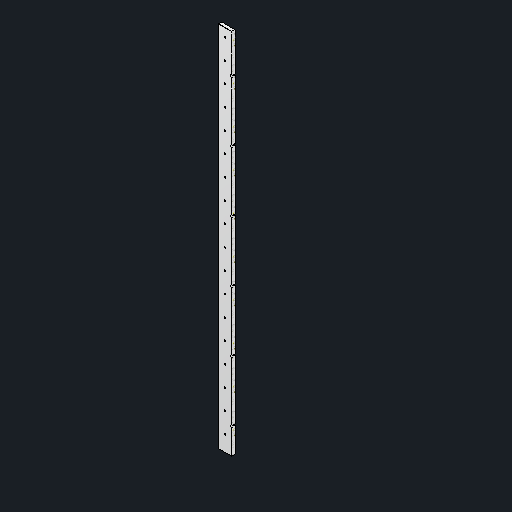
# Autodesk Inventor part: monotaro-bellows-plate
Saved by Autodesk Inventor 2027.1 (Build 311270010, 270A)
## iProperties
Created: 2026-11-14
Part Number: monotaro-bellows-plate
Material: Aluminum 6061
Description: MonotaRO review plate; verify fastener threads, vendor outlines and travel before machining
Document SubType Name: Modeling
Designer: queezz
Density: 2.7 g/cm^3
Appearance: Aluminum - Flat
Author: queezz
Autodesk Inventor part; units mm, degrees
ref_plane "215 x 1235 blank plane" through (0, 0, -55) normal (0, 0, 1) x (1, 0, 0)
sketch "215 x 1235 blank" plane through (0, 0, -55) normal (0, 0, 1) x (1, 0, 0)
  line L0 (-107.5, -339.7289) -> (107.5, -339.7289)
  line L1 (107.5, -339.7289) -> (107.5, 895.2711)
  line L2 (107.5, 895.2711) -> (-107.5, 895.2711)
  line L3 (-107.5, 895.2711) -> (-107.5, -339.7289)
  constraints: 8 end point, 2 parallel, 1 horizontal, 1 perpendicular
extrude "Table plate" add sketch "215 x 1235 blank" along normal blind 10
ref_plane "Wheel sweep edge relief plane" through (0, 0, -45) normal (0, 0, 1) x (1, 0, 0)
sketch "Wheel sweep edge relief" plane through (0, 0, -45) normal (0, 0, 1) x (1, 0, 0)
  line L0 (-75, -342) -> (75, -342)
  line L1 (75, -342) -> (75, -197)
  line L2 (75, -197) -> (-75, -197)
  line L3 (-75, -197) -> (-75, -342)
  constraints: 8 end point, 2 parallel, 1 horizontal, 1 perpendicular
extrude "150 mm open wheel notch" [suppressed]
ref_plane "SBC rail M5 tap pilots layout plane" through (0, 0, -45) normal (0, 0, 1) x (1, 0, 0)
sketch "SBC rail M5 tap pilots layout" plane through (0, 0, -45) normal (0, 0, 1) x (1, 0, 0)
  circle A0 centre (-87.5, -149.7289) radius 2.1
  circle A1 centre (-87.5, -89.7289) radius 2.1
  circle A2 centre (-87.5, -29.7289) radius 2.1
  circle A3 centre (-87.5, 30.2711) radius 2.1
  circle A4 centre (-87.5, 90.2711) radius 2.1
  circle A5 centre (-87.5, 150.2711) radius 2.1
  circle A6 centre (-87.5, 210.2711) radius 2.1
  circle A7 centre (-87.5, 270.2711) radius 2.1
  circle A8 centre (-87.5, 330.2711) radius 2.1
  circle A9 centre (-87.5, 390.2711) radius 2.1
  circle A10 centre (-87.5, 450.2711) radius 2.1
  circle A11 centre (-87.5, 510.2711) radius 2.1
  circle A12 centre (-87.5, 570.2711) radius 2.1
  circle A13 centre (-87.5, 630.2711) radius 2.1
  circle A14 centre (-87.5, 690.2711) radius 2.1
  circle A15 centre (-87.5, 750.2711) radius 2.1
  circle A16 centre (-87.5, 810.2711) radius 2.1
  circle A17 centre (-87.5, 870.2711) radius 2.1
  circle A18 centre (87.5, -149.7289) radius 2.1
  circle A19 centre (87.5, -89.7289) radius 2.1
  circle A20 centre (87.5, -29.7289) radius 2.1
  circle A21 centre (87.5, 30.2711) radius 2.1
  circle A22 centre (87.5, 90.2711) radius 2.1
  circle A23 centre (87.5, 150.2711) radius 2.1
  circle A24 centre (87.5, 210.2711) radius 2.1
  circle A25 centre (87.5, 270.2711) radius 2.1
  circle A26 centre (87.5, 330.2711) radius 2.1
  circle A27 centre (87.5, 390.2711) radius 2.1
  circle A28 centre (87.5, 450.2711) radius 2.1
  circle A29 centre (87.5, 510.2711) radius 2.1
  circle A30 centre (87.5, 570.2711) radius 2.1
  circle A31 centre (87.5, 630.2711) radius 2.1
  circle A32 centre (87.5, 690.2711) radius 2.1
  circle A33 centre (87.5, 750.2711) radius 2.1
  circle A34 centre (87.5, 810.2711) radius 2.1
  circle A35 centre (87.5, 870.2711) radius 2.1
  constraints: 36 centre point
extrude "SBC rail M5 tap pilots" [suppressed]
ref_plane "Lead screw blocks M6 tap pilots layout plane" through (0, 0, -45) normal (0, 0, 1) x (1, 0, 0)
sketch "Lead screw blocks M6 tap pilots layout" plane through (0, 0, -45) normal (0, 0, 1) x (1, 0, 0)
  circle A0 centre (-23, -169.7489) radius 2.5
  circle A1 centre (-23, 750.2911) radius 2.5
  circle A2 centre (23, -169.7489) radius 2.5
  circle A3 centre (23, 750.2911) radius 2.5
  constraints: 4 centre point
extrude "Lead screw blocks M6 tap pilots" [suppressed]
ref_plane "Plate to T-slot M5 clearance layout plane" through (0, 0, -45) normal (0, 0, 1) x (1, 0, 0)
sketch "Plate to T-slot M5 clearance layout" plane through (0, 0, -45) normal (0, 0, 1) x (1, 0, 0)
  circle A0 centre (-92.5, -119.7289) radius 2.75
  circle A1 centre (-92.5, 60.2711) radius 2.75
  circle A2 centre (-92.5, 240.2711) radius 2.75
  circle A3 centre (-92.5, 420.2711) radius 2.75
  circle A4 centre (-92.5, 600.2711) radius 2.75
  circle A5 centre (-92.5, 780.2711) radius 2.75
  circle A6 centre (92.5, -119.7289) radius 2.75
  circle A7 centre (92.5, 60.2711) radius 2.75
  circle A8 centre (92.5, 240.2711) radius 2.75
  circle A9 centre (92.5, 420.2711) radius 2.75
  circle A10 centre (92.5, 600.2711) radius 2.75
  circle A11 centre (92.5, 780.2711) radius 2.75
  constraints: 12 centre point
extrude "Plate to T-slot M5 clearance" [suppressed]
ref_plane "Flush fastener head envelope layout plane" through (0, 0, -45) normal (0, 0, 1) x (1, 0, 0)
sketch "Flush fastener head envelope layout" plane through (0, 0, -45) normal (0, 0, 1) x (1, 0, 0)
  circle A0 centre (-92.5, -119.7289) radius 5
  circle A1 centre (-92.5, 60.2711) radius 5
  circle A2 centre (-92.5, 240.2711) radius 5
  circle A3 centre (-92.5, 420.2711) radius 5
  circle A4 centre (-92.5, 600.2711) radius 5
  circle A5 centre (-92.5, 780.2711) radius 5
  circle A6 centre (92.5, -119.7289) radius 5
  circle A7 centre (92.5, 60.2711) radius 5
  circle A8 centre (92.5, 240.2711) radius 5
  circle A9 centre (92.5, 420.2711) radius 5
  circle A10 centre (92.5, 600.2711) radius 5
  circle A11 centre (92.5, 780.2711) radius 5
  constraints: 12 centre point
extrude "Flush fastener head envelope" [suppressed]
ref_plane "Work Plane7" through (0, 0, -45) normal (0, 0, 1) x (1, 0, 0)
sketch "Straight wheel-end trim layout" plane through (0, 0, -45) normal (0, 0, 1) x (1, 0, 0)
  line L0 (-110, -350) -> (110, -350)
  line L1 (110, -350) -> (110, -196.729)
  line L2 (110, -196.729) -> (-110, -196.729)
  line L3 (-110, -196.729) -> (-110, -350)
  constraints: 8 end point, 2 parallel, 1 horizontal, 1 perpendicular
extrude "Straight wheel-end trim" cut sketch "Straight wheel-end trim layout" against normal blind 10
ref_plane "Work Plane8" through (0, 0, -45) normal (0, 0, 1) x (1, 0, 0)
sketch "SBC rail M6 tap pilot layout" plane through (0, 0, -45) normal (0, 0, 1) x (1, 0, 0)
  circle A0 centre (-87.5, -149.7289) radius 2.5
  circle A1 centre (-87.5, -89.7289) radius 2.5
  circle A2 centre (-87.5, -29.7289) radius 2.5
  circle A3 centre (-87.5, 30.2711) radius 2.5
  circle A4 centre (-87.5, 90.2711) radius 2.5
  circle A5 centre (-87.5, 150.2711) radius 2.5
  circle A6 centre (-87.5, 210.2711) radius 2.5
  circle A7 centre (-87.5, 270.2711) radius 2.5
  circle A8 centre (-87.5, 330.2711) radius 2.5
  circle A9 centre (-87.5, 390.2711) radius 2.5
  circle A10 centre (-87.5, 450.2711) radius 2.5
  circle A11 centre (-87.5, 510.2711) radius 2.5
  circle A12 centre (-87.5, 570.2711) radius 2.5
  circle A13 centre (-87.5, 630.2711) radius 2.5
  circle A14 centre (-87.5, 690.2711) radius 2.5
  circle A15 centre (-87.5, 750.2711) radius 2.5
  circle A16 centre (-87.5, 810.2711) radius 2.5
  circle A17 centre (-87.5, 870.2711) radius 2.5
  circle A18 centre (87.5, -149.7289) radius 2.5
  circle A19 centre (87.5, -89.7289) radius 2.5
  circle A20 centre (87.5, -29.7289) radius 2.5
  circle A21 centre (87.5, 30.2711) radius 2.5
  circle A22 centre (87.5, 90.2711) radius 2.5
  circle A23 centre (87.5, 150.2711) radius 2.5
  circle A24 centre (87.5, 210.2711) radius 2.5
  circle A25 centre (87.5, 270.2711) radius 2.5
  circle A26 centre (87.5, 330.2711) radius 2.5
  circle A27 centre (87.5, 390.2711) radius 2.5
  circle A28 centre (87.5, 450.2711) radius 2.5
  circle A29 centre (87.5, 510.2711) radius 2.5
  circle A30 centre (87.5, 570.2711) radius 2.5
  circle A31 centre (87.5, 630.2711) radius 2.5
  circle A32 centre (87.5, 690.2711) radius 2.5
  circle A33 centre (87.5, 750.2711) radius 2.5
  circle A34 centre (87.5, 810.2711) radius 2.5
  circle A35 centre (87.5, 870.2711) radius 2.5
  constraints: 36 centre point
extrude "36 rail M6 tap pilots" [suppressed]
ref_plane "Work Plane9" through (0, 0, -44.9) normal (0, 0, 1) x (1, 0, 0)
sketch "Accessible profile screw layout" plane through (0, 0, -44.9) normal (0, 0, 1) x (1, 0, 0)
  circle A0 centre (-65, -119.7289) radius 2.75
  circle A1 centre (-65, 60.2711) radius 2.75
  circle A2 centre (-65, 240.2711) radius 2.75
  circle A3 centre (-65, 420.2711) radius 2.75
  circle A4 centre (-65, 600.2711) radius 2.75
  circle A5 centre (-65, 780.2711) radius 2.75
  circle A6 centre (65, -119.7289) radius 2.75
  circle A7 centre (65, 60.2711) radius 2.75
  circle A8 centre (65, 240.2711) radius 2.75
  circle A9 centre (65, 420.2711) radius 2.75
  circle A10 centre (65, 600.2711) radius 2.75
  circle A11 centre (65, 780.2711) radius 2.75
  constraints: 12 centre point
extrude "12 accessible M5 profile clearances" [suppressed]
ref_plane "Work Plane10" through (0, 0, -44.9) normal (0, 0, 1) x (1, 0, 0)
sketch "Flush M5 profile seats" plane through (0, 0, -44.9) normal (0, 0, 1) x (1, 0, 0)
  circle A0 centre (-65, -119.7289) radius 5.2
  circle A1 centre (-65, 60.2711) radius 5.2
  circle A2 centre (-65, 240.2711) radius 5.2
  circle A3 centre (-65, 420.2711) radius 5.2
  circle A4 centre (-65, 600.2711) radius 5.2
  circle A5 centre (-65, 780.2711) radius 5.2
  circle A6 centre (65, -119.7289) radius 5.2
  circle A7 centre (65, 60.2711) radius 5.2
  circle A8 centre (65, 240.2711) radius 5.2
  circle A9 centre (65, 420.2711) radius 5.2
  circle A10 centre (65, 600.2711) radius 5.2
  circle A11 centre (65, 780.2711) radius 5.2
  constraints: 12 centre point
extrude "Extrusion10" [suppressed]
extrude "Seats for DIN 7991 socket flat heads" [suppressed]
ref_plane "Work Plane11" through (0, 0, -44.9) normal (0, 0, 1) x (1, 0, 0)
sketch "Thrust backing fixings" plane through (0, 0, -44.9) normal (0, 0, 1) x (1, 0, 0)
  circle A0 centre (-23, -169.7489) radius 3.3
  circle A1 centre (23, -169.7489) radius 3.3
  circle A2 centre (-42, -179.7489) radius 2.75
  circle A3 centre (-42, -139.7489) radius 2.75
  circle A4 centre (42, -179.7489) radius 2.75
  circle A5 centre (42, -139.7489) radius 2.75
  circle A6 centre (-23, 750.2911) radius 3.3
  circle A7 centre (23, 750.2911) radius 3.3
  circle A8 centre (-42, 740.2911) radius 2.75
  circle A9 centre (-42, 780.2911) radius 2.75
  circle A10 centre (42, 740.2911) radius 2.75
  circle A11 centre (42, 780.2911) radius 2.75
  constraints: 12 centre point
extrude "Through holes for reinforced thrust mounts" [suppressed]
ref_plane "Work Plane12" through (0, 0, -44.9) normal (0, 0, 1) x (1, 0, 0)
sketch "Thrust backing flat head seats" plane through (0, 0, -44.9) normal (0, 0, 1) x (1, 0, 0)
  circle A0 centre (-42, -179.7489) radius 5.2
  circle A1 centre (-42, -139.7489) radius 5.2
  circle A2 centre (42, -179.7489) radius 5.2
  circle A3 centre (42, -139.7489) radius 5.2
  circle A4 centre (-42, 740.2911) radius 5.2
  circle A5 centre (-42, 780.2911) radius 5.2
  circle A6 centre (42, 740.2911) radius 5.2
  circle A7 centre (42, 780.2911) radius 5.2
  constraints: 8 centre point
extrude "Eight flush backing plate screw seats" [suppressed]
fillet "R2 exposed plan corners" radius 2 4 edges at (-107.5, -196.729, -50) (107.5, -196.729, -50) (-107.5, 895.2711, -50) (107.5, 895.2711, -50)
chamfer "C0.4 outside perimeter" distance 0.4 angle 45 16 edges at (106.9142, 894.6853, -45) (106.9142, 894.6853, -55) (0, 895.2711, -55) (0, 895.2711, -45) (107.5, 349.271, -55) (106.9142, -196.1432, -55) (0, -196.729, -55) (-106.9142, -196.1432, -55) (-107.5, 349.271, -55) (-106.9142, 894.6853, -55) (-106.9142, 894.6853, -45) (-107.5, 349.271, -45) (106.9142, -196.1432, -45) (107.5, 349.271, -45) (-106.9142, -196.1432, -45) (0, -196.729, -45)
sketch "Rail mounting — M6 × 1 through centers" plane through (0, 0, -45) normal (0, 0, 1) x (1, 0, 0)
  point P0 (-87.5, -149.7289)
  point P1 (-87.5, -89.7289)
  point P2 (-87.5, -29.7289)
  point P3 (-87.5, 30.2711)
  point P4 (-87.5, 90.2711)
  point P5 (-87.5, 150.2711)
  point P6 (-87.5, 210.2711)
  point P7 (-87.5, 270.2711)
  point P8 (-87.5, 330.2711)
  point P9 (-87.5, 390.2711)
  point P10 (-87.5, 450.2711)
  point P11 (-87.5, 510.2711)
  point P12 (-87.5, 570.2711)
  point P13 (-87.5, 630.2711)
  point P14 (-87.5, 690.2711)
  point P15 (-87.5, 750.2711)
  point P16 (-87.5, 810.2711)
  point P17 (-87.5, 870.2711)
  point P18 (87.5, -149.7289)
  point P19 (87.5, -89.7289)
  point P20 (87.5, -29.7289)
  point P21 (87.5, 30.2711)
  point P22 (87.5, 90.2711)
  point P23 (87.5, 150.2711)
  point P24 (87.5, 210.2711)
  point P25 (87.5, 270.2711)
  point P26 (87.5, 330.2711)
  point P27 (87.5, 390.2711)
  point P28 (87.5, 450.2711)
  point P29 (87.5, 510.2711)
  point P30 (87.5, 570.2711)
  point P31 (87.5, 630.2711)
  point P32 (87.5, 690.2711)
  point P33 (87.5, 750.2711)
  point P34 (87.5, 810.2711)
  point P35 (87.5, 870.2711)
  constraints: 36 other
hole "Rail mounting — M6 × 1 through" at (-87.5, -149.7289, -45) at (-87.5, -89.7289, -45) at (-87.5, -29.7289, -45) at (-87.5, 30.2711, -45) at (-87.5, 90.2711, -45) at (-87.5, 150.2711, -45) at (-87.5, 210.2711, -45) at (-87.5, 270.2711, -45) at (-87.5, 330.2711, -45) at (-87.5, 390.2711, -45) at (-87.5, 450.2711, -45) at (-87.5, 510.2711, -45) at (-87.5, 570.2711, -45) at (-87.5, 630.2711, -45) at (-87.5, 690.2711, -45) at (-87.5, 750.2711, -45) at (-87.5, 810.2711, -45) at (-87.5, 870.2711, -45) at (87.5, -149.7289, -45) at (87.5, -89.7289, -45) at (87.5, -29.7289, -45) at (87.5, 30.2711, -45) at (87.5, 90.2711, -45) at (87.5, 150.2711, -45) at (87.5, 210.2711, -45) at (87.5, 270.2711, -45) at (87.5, 330.2711, -45) at (87.5, 390.2711, -45) at (87.5, 450.2711, -45) at (87.5, 510.2711, -45) at (87.5, 570.2711, -45) at (87.5, 630.2711, -45) at (87.5, 690.2711, -45) at (87.5, 750.2711, -45) at (87.5, 810.2711, -45) at (87.5, 870.2711, -45) direction (0, 0, -1) diameter 4.917 end through all thread size "M6x1" class "6H" standard "ISO Metric profile"
sketch "Extrusion mounting — M5 countersinks centers" plane through (0, 0, -45) normal (0, 0, 1) x (1, 0, 0)
  point P0 (-65, -119.7289)
  point P1 (-65, 60.2711)
  point P2 (-65, 240.2711)
  point P3 (-65, 420.2711)
  point P4 (-65, 600.2711)
  point P5 (-65, 780.2711)
  point P6 (65, -119.7289)
  point P7 (65, 60.2711)
  point P8 (65, 240.2711)
  point P9 (65, 420.2711)
  point P10 (65, 600.2711)
  point P11 (65, 780.2711)
  constraints: 12 other
hole "Extrusion mounting — M5 countersinks" at (-65, -119.7289, -45) at (-65, 60.2711, -45) at (-65, 240.2711, -45) at (-65, 420.2711, -45) at (-65, 600.2711, -45) at (-65, 780.2711, -45) at (65, -119.7289, -45) at (65, 60.2711, -45) at (65, 240.2711, -45) at (65, 420.2711, -45) at (65, 600.2711, -45) at (65, 780.2711, -45) direction (0, 0, -1) diameter 5.5 end through all countersink diameter 11.2 countersink angle 90
sketch "Thrust backing — M5 countersinks centers" plane through (0, 0, -45) normal (0, 0, 1) x (1, 0, 0)
  point P0 (-42, -179.7489)
  point P1 (-42, -139.7489)
  point P2 (42, -179.7489)
  point P3 (42, -139.7489)
  point P4 (-42, 740.2911)
  point P5 (-42, 780.2911)
  point P6 (42, 740.2911)
  point P7 (42, 780.2911)
  constraints: 8 other
hole "Thrust backing — M5 countersinks" at (-42, -179.7489, -45) at (-42, -139.7489, -45) at (42, -179.7489, -45) at (42, -139.7489, -45) at (-42, 740.2911, -45) at (-42, 780.2911, -45) at (42, 740.2911, -45) at (42, 780.2911, -45) direction (0, 0, -1) diameter 5.5 end through all countersink diameter 11.2 countersink angle 90
sketch "Thrust support — Ø6.6 through centers" plane through (0, 0, -45) normal (0, 0, 1) x (1, 0, 0)
  point P0 (-23, -169.7489)
  point P1 (23, -169.7489)
  point P2 (-23, 750.2911)
  point P3 (23, 750.2911)
  constraints: 4 other
hole "Thrust support — Ø6.6 through" at (-23, -169.7489, -45) at (23, -169.7489, -45) at (-23, 750.2911, -45) at (23, 750.2911, -45) direction (0, 0, -1) diameter 6.6 end through all
body "Solid1"
